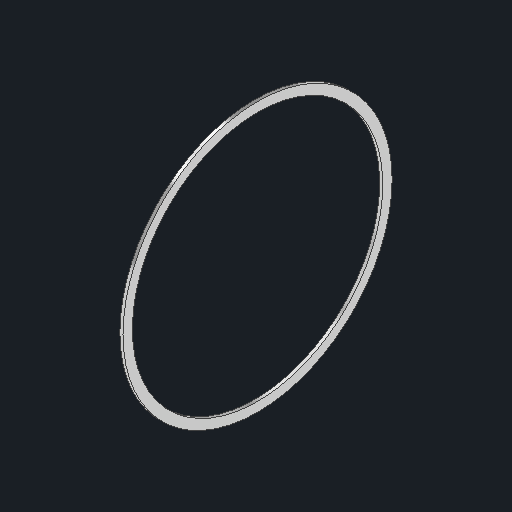
# Autodesk Inventor part: ra_joint_ring
Saved by Autodesk Inventor 2027.1 (Build 311270010, 270A)
## iProperties
Created: 2026-11-04
Part Number: ra_joint_ring
Material: Generic
Description: Bright ring at the RA rotation joint
Document SubType Name: Modeling
Designer: Claude (from photos)
Density: 1 g/cm^3
Appearance: Chrome - Polished
Author: alexg
Autodesk Inventor part; units mm, degrees
ref_plane "XZ Plane" through (0, 0, 0) normal (0, 1, 0) x (-1, 0, 0)
ref_plane "XY Plane" through (0, 0, 0) normal (0, 0, 1) x (1, 0, 0)
ref_plane "Work Plane1" through (94, 0, 0) normal (1, 0, 0) x (0, 1, 0)
sketch "RA joint ring sketch" plane through (94, 0, 0) normal (1, 0, 0) x (0, 1, 0)
  circle A0 centre (0, 0) radius 43
  circle A1 centre (0, 0) radius 40
  constraints: 2 centre point
extrude "RA joint ring" add sketch "RA joint ring sketch" along normal blind 1
body "Solid1"
